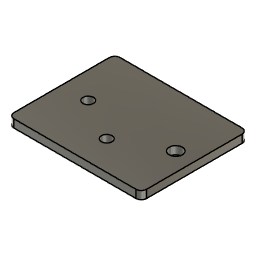
SMPS_supprt-2_2025-02-12 (Autodesk Fusion 360 design; units mm, degrees)
Autodesk Fusion 360 part; units mm, degrees
sketch "스케치1" plane through (0, 0, 0) normal (0, 0, 1) x (1, 0, 0)
  line L0 (0, 0) -> (50, 0)
  line L1 (0, 40) -> (0, 0)
  line L2 (0, -50) -> (0, -51.5624)
  line L3 (50, 40) -> (50, 0)
  line L4 (0, 40) -> (50, 40)
  circle A0 centre (10, 20) radius 2
  circle A1 centre (43, 20) radius 2.5
  circle A2 centre (26, 11) radius 2
  dimension "d1" = 4
  dimension "d3" = 5
  dimension "d4" = 4
  constraint horizontal L0
  constraint vertical L1
  constraint vertical L3
  constraint horizontal L4
  constraint coincident L0 L1.end
  constraint coincident L1 L0.start
  measures "d1" diameter of A0
  measures "d3" diameter of A1
  measures "d4" diameter of A2
extrude "돌출1" add sketch "스케치1" along normal blind 3
fillet "필렛1" radius 2 3 edges at (50, 0, 1.5) (50, 40, 1.5) (0, 0, 1.5)
fillet "필렛2" radius 2 1 edges at (0, 40, 1.5)
